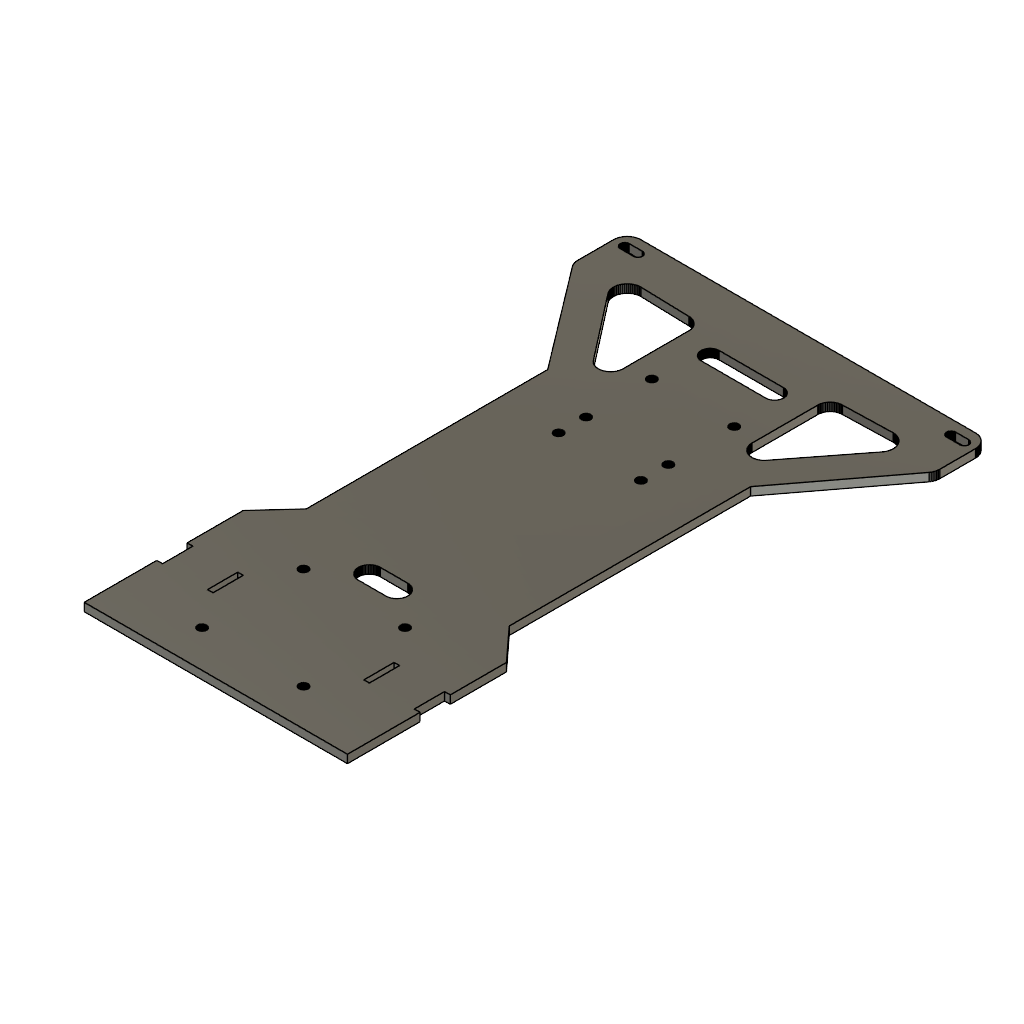
modelo-3d (Autodesk Fusion 360 archive; units mm, degrees)
design "Robot sigue lineas1"
part number: 2026-11-21-15-19-23-234
Autodesk Fusion 360 part; units mm, degrees
(part 1 of 2)
sketch "Sketch1" plane through (0, 0, 0) normal (0, 0, 1) x (1, 0, 0)
  line L0 (48, 26.5) -> (45.9, 26.5)
  line L1 (45.9, 26.5) -> (45.9, 37.5)
  line L2 (45.9, 37.5) -> (48, 37.5)
  line L3 (48, 37.5) -> (48, 58)
  line L4 (48, 58) -> (37, 70)
  line L5 (37, 70) -> (37, 158)
  line L6 (37, 158) -> (65.0451, 195.061)
  line L7 (65.0451, 195.061) -> (65.3301, 195.5)
  line L8 (65.3301, 195.5) -> (65.5677, 195.966)
  line L9 (65.5677, 195.966) -> (65.7553, 196.455)
  line L10 (65.7553, 196.455) -> (65.8907, 196.96)
  line L11 (65.8907, 196.96) -> (65.9726, 197.477)
  line L12 (65.9726, 197.477) -> (66, 198)
  line L13 (66, 198) -> (66, 211)
  line L14 (66, 211) -> (65.9726, 211.523)
  line L15 (65.9726, 211.523) -> (65.8907, 212.04)
  line L16 (65.8907, 212.04) -> (65.7553, 212.545)
  line L17 (65.7553, 212.545) -> (65.5677, 213.034)
  line L18 (65.5677, 213.034) -> (65.3301, 213.5)
  line L19 (65.3301, 213.5) -> (65.0451, 213.939)
  line L20 (65.0451, 213.939) -> (64.7157, 214.346)
  line L21 (64.7157, 214.346) -> (64.3457, 214.716)
  line L22 (64.3457, 214.716) -> (63.9389, 215.045)
  line L23 (63.9389, 215.045) -> (63.5, 215.33)
  line L24 (63.5, 215.33) -> (63.0337, 215.568)
  line L25 (63.0337, 215.568) -> (62.5451, 215.755)
  line L26 (62.5451, 215.755) -> (62.0396, 215.891)
  line L27 (62.0396, 215.891) -> (61.5226, 215.973)
  line L28 (61.5226, 215.973) -> (61, 216)
  line L29 (61, 216) -> (-61, 216)
  line L30 (-61, 216) -> (-61.5226, 215.973)
  line L31 (-61.5226, 215.973) -> (-62.0396, 215.891)
  line L32 (-62.0396, 215.891) -> (-62.5451, 215.755)
  line L33 (-62.5451, 215.755) -> (-63.0337, 215.568)
  line L34 (-63.0337, 215.568) -> (-63.5, 215.33)
  line L35 (-63.5, 215.33) -> (-63.9389, 215.045)
  line L36 (-63.9389, 215.045) -> (-64.3457, 214.716)
  line L37 (-64.3457, 214.716) -> (-64.7157, 214.346)
  line L38 (-64.7157, 214.346) -> (-65.0451, 213.939)
  line L39 (-65.0451, 213.939) -> (-65.3301, 213.5)
  line L40 (-65.3301, 213.5) -> (-65.5677, 213.034)
  line L41 (-65.5677, 213.034) -> (-65.7553, 212.545)
  line L42 (-65.7553, 212.545) -> (-65.8907, 212.04)
  line L43 (-65.8907, 212.04) -> (-65.9726, 211.523)
  line L44 (-65.9726, 211.523) -> (-66, 211)
  line L45 (-66, 211) -> (-66, 198)
  line L46 (-66, 198) -> (-65.9726, 197.477)
  line L47 (-65.9726, 197.477) -> (-65.8907, 196.96)
  line L48 (-65.8907, 196.96) -> (-65.7553, 196.455)
  line L49 (-65.7553, 196.455) -> (-65.5677, 195.966)
  line L50 (-65.5677, 195.966) -> (-65.3301, 195.5)
  line L51 (-65.3301, 195.5) -> (-65.0451, 195.061)
  line L52 (-65.0451, 195.061) -> (-37, 158)
  line L53 (-37, 158) -> (-37, 70)
  line L54 (-37, 70) -> (-48, 58)
  line L55 (-48, 58) -> (-48, 37.5)
  line L56 (-48, 37.5) -> (-45.9, 37.5)
  line L57 (-45.9, 37.5) -> (-45.9, 26.5)
  line L58 (-45.9, 26.5) -> (-48, 26.5)
  line L59 (-48, 26.5) -> (-48, 0)
  line L60 (-48, 0) -> (48, 0)
  line L61 (48, 0) -> (48, 26.5)
  line L62 (-61.9, 209.4) -> (-62.0672, 209.409)
  line L63 (-62.0672, 209.409) -> (-62.2327, 209.435)
  line L64 (-62.2327, 209.435) -> (-62.3944, 209.478)
  line L65 (-62.3944, 209.478) -> (-62.5508, 209.538)
  line L66 (-62.5508, 209.538) -> (-62.7, 209.614)
  line L67 (-62.7, 209.614) -> (-62.8405, 209.706)
  line L68 (-62.8405, 209.706) -> (-62.9706, 209.811)
  line L69 (-62.9706, 209.811) -> (-63.089, 209.929)
  line L70 (-63.089, 209.929) -> (-63.1944, 210.06)
  line L71 (-63.1944, 210.06) -> (-63.2856, 210.2)
  line L72 (-63.2856, 210.2) -> (-63.3617, 210.349)
  line L73 (-63.3617, 210.349) -> (-63.4217, 210.506)
  line L74 (-63.4217, 210.506) -> (-63.465, 210.667)
  line L75 (-63.465, 210.667) -> (-63.4912, 210.833)
  line L76 (-63.4912, 210.833) -> (-63.5, 211)
  line L77 (-63.5, 211) -> (-63.4912, 211.167)
  line L78 (-63.4912, 211.167) -> (-63.465, 211.333)
  line L79 (-63.465, 211.333) -> (-63.4217, 211.494)
  line L80 (-63.4217, 211.494) -> (-63.3617, 211.651)
  line L81 (-63.3617, 211.651) -> (-63.2856, 211.8)
  line L82 (-63.2856, 211.8) -> (-63.1944, 211.94)
  line L83 (-63.1944, 211.94) -> (-63.089, 212.071)
  line L84 (-63.089, 212.071) -> (-62.9706, 212.189)
  line L85 (-62.9706, 212.189) -> (-62.8405, 212.294)
  line L86 (-62.8405, 212.294) -> (-62.7, 212.386)
  line L87 (-62.7, 212.386) -> (-62.5508, 212.462)
  line L88 (-62.5508, 212.462) -> (-62.3944, 212.522)
  line L89 (-62.3944, 212.522) -> (-62.2327, 212.565)
  line L90 (-62.2327, 212.565) -> (-62.0672, 212.591)
  line L91 (-62.0672, 212.591) -> (-61.9, 212.6)
  line L92 (-61.9, 212.6) -> (-57.1, 212.6)
  line L93 (-57.1, 212.6) -> (-56.9328, 212.591)
  line L94 (-56.9328, 212.591) -> (-56.7673, 212.565)
  line L95 (-56.7673, 212.565) -> (-56.6056, 212.522)
  line L96 (-56.6056, 212.522) -> (-56.4492, 212.462)
  line L97 (-56.4492, 212.462) -> (-56.3, 212.386)
  line L98 (-56.3, 212.386) -> (-56.1595, 212.294)
  line L99 (-56.1595, 212.294) -> (-56.0294, 212.189)
  line L100 (-56.0294, 212.189) -> (-55.911, 212.071)
  line L101 (-55.911, 212.071) -> (-55.8056, 211.94)
  line L102 (-55.8056, 211.94) -> (-55.7144, 211.8)
  line L103 (-55.7144, 211.8) -> (-55.6383, 211.651)
  line L104 (-55.6383, 211.651) -> (-55.5783, 211.494)
  line L105 (-55.5783, 211.494) -> (-55.535, 211.333)
  line L106 (-55.535, 211.333) -> (-55.5088, 211.167)
  line L107 (-55.5088, 211.167) -> (-55.5, 211)
  line L108 (-55.5, 211) -> (-55.5088, 210.833)
  line L109 (-55.5088, 210.833) -> (-55.535, 210.667)
  line L110 (-55.535, 210.667) -> (-55.5783, 210.506)
  line L111 (-55.5783, 210.506) -> (-55.6383, 210.349)
  line L112 (-55.6383, 210.349) -> (-55.7144, 210.2)
  line L113 (-55.7144, 210.2) -> (-55.8056, 210.06)
  line L114 (-55.8056, 210.06) -> (-55.911, 209.929)
  line L115 (-55.911, 209.929) -> (-56.0294, 209.811)
  line L116 (-56.0294, 209.811) -> (-56.1595, 209.706)
  line L117 (-56.1595, 209.706) -> (-56.3, 209.614)
  line L118 (-56.3, 209.614) -> (-56.4492, 209.538)
  line L119 (-56.4492, 209.538) -> (-56.6056, 209.478)
  line L120 (-56.6056, 209.478) -> (-56.7673, 209.435)
  line L121 (-56.7673, 209.435) -> (-56.9328, 209.409)
  line L122 (-56.9328, 209.409) -> (-57.1, 209.4)
  line L123 (-57.1, 209.4) -> (-61.9, 209.4)
  line L124 (57.1, 209.4) -> (56.9328, 209.409)
  line L125 (56.9328, 209.409) -> (56.7673, 209.435)
  line L126 (56.7673, 209.435) -> (56.6056, 209.478)
  line L127 (56.6056, 209.478) -> (56.4492, 209.538)
  line L128 (56.4492, 209.538) -> (56.3, 209.614)
  line L129 (56.3, 209.614) -> (56.1595, 209.706)
  line L130 (56.1595, 209.706) -> (56.0294, 209.811)
  line L131 (56.0294, 209.811) -> (55.911, 209.929)
  line L132 (55.911, 209.929) -> (55.8056, 210.06)
  line L133 (55.8056, 210.06) -> (55.7144, 210.2)
  line L134 (55.7144, 210.2) -> (55.6383, 210.349)
  line L135 (55.6383, 210.349) -> (55.5783, 210.506)
  line L136 (55.5783, 210.506) -> (55.535, 210.667)
  line L137 (55.535, 210.667) -> (55.5088, 210.833)
  line L138 (55.5088, 210.833) -> (55.5, 211)
  line L139 (55.5, 211) -> (55.5088, 211.167)
  line L140 (55.5088, 211.167) -> (55.535, 211.333)
  line L141 (55.535, 211.333) -> (55.5783, 211.494)
  line L142 (55.5783, 211.494) -> (55.6383, 211.651)
  line L143 (55.6383, 211.651) -> (55.7144, 211.8)
  line L144 (55.7144, 211.8) -> (55.8056, 211.94)
  line L145 (55.8056, 211.94) -> (55.911, 212.071)
  line L146 (55.911, 212.071) -> (56.0294, 212.189)
  line L147 (56.0294, 212.189) -> (56.1595, 212.294)
  line L148 (56.1595, 212.294) -> (56.3, 212.386)
  line L149 (56.3, 212.386) -> (56.4492, 212.462)
  line L150 (56.4492, 212.462) -> (56.6056, 212.522)
  line L151 (56.6056, 212.522) -> (56.7673, 212.565)
  line L152 (56.7673, 212.565) -> (56.9328, 212.591)
  line L153 (56.9328, 212.591) -> (57.1, 212.6)
  line L154 (57.1, 212.6) -> (61.9, 212.6)
  line L155 (61.9, 212.6) -> (62.0672, 212.591)
  line L156 (62.0672, 212.591) -> (62.2327, 212.565)
  line L157 (62.2327, 212.565) -> (62.3944, 212.522)
  line L158 (62.3944, 212.522) -> (62.5508, 212.462)
  line L159 (62.5508, 212.462) -> (62.7, 212.386)
  line L160 (62.7, 212.386) -> (62.8405, 212.294)
  line L161 (62.8405, 212.294) -> (62.9706, 212.189)
  line L162 (62.9706, 212.189) -> (63.089, 212.071)
  line L163 (63.089, 212.071) -> (63.1944, 211.94)
  line L164 (63.1944, 211.94) -> (63.2856, 211.8)
  line L165 (63.2856, 211.8) -> (63.3617, 211.651)
  line L166 (63.3617, 211.651) -> (63.4217, 211.494)
  line L167 (63.4217, 211.494) -> (63.465, 211.333)
  line L168 (63.465, 211.333) -> (63.4912, 211.167)
  line L169 (63.4912, 211.167) -> (63.5, 211)
  line L170 (63.5, 211) -> (63.4912, 210.833)
  line L171 (63.4912, 210.833) -> (63.465, 210.667)
  line L172 (63.465, 210.667) -> (63.4217, 210.506)
  line L173 (63.4217, 210.506) -> (63.3617, 210.349)
  line L174 (63.3617, 210.349) -> (63.2856, 210.2)
  line L175 (63.2856, 210.2) -> (63.1944, 210.06)
  line L176 (63.1944, 210.06) -> (63.089, 209.929)
  line L177 (63.089, 209.929) -> (62.9706, 209.811)
  line L178 (62.9706, 209.811) -> (62.8405, 209.706)
  line L179 (62.8405, 209.706) -> (62.7, 209.614)
  line L180 (62.7, 209.614) -> (62.5508, 209.538)
  line L181 (62.5508, 209.538) -> (62.3944, 209.478)
  line L182 (62.3944, 209.478) -> (62.2327, 209.435)
  line L183 (62.2327, 209.435) -> (62.0672, 209.409)
  line L184 (62.0672, 209.409) -> (61.9, 209.4)
  line L185 (61.9, 209.4) -> (57.1, 209.4)
  line L186 (-28.4704, 167.525) -> (-28.9356, 167.598)
  line L187 (-28.9356, 167.598) -> (-29.3906, 167.72)
  line L188 (-29.3906, 167.72) -> (-29.8303, 167.889)
  line L189 (-29.8303, 167.889) -> (-30.25, 168.103)
  line L190 (-30.25, 168.103) -> (-30.645, 168.359)
  line L191 (-30.645, 168.359) -> (-31.0111, 168.656)
  line L192 (-31.0111, 168.656) -> (-31.3442, 168.989)
  line L193 (-31.3442, 168.989) -> (-31.6406, 169.355)
  line L194 (-31.6406, 169.355) -> (-50.0451, 193.061)
  line L195 (-50.0451, 193.061) -> (-50.3301, 193.5)
  line L196 (-50.3301, 193.5) -> (-50.5677, 193.966)
  line L197 (-50.5677, 193.966) -> (-50.7553, 194.455)
  line L198 (-50.7553, 194.455) -> (-50.8907, 194.96)
  line L199 (-50.8907, 194.96) -> (-50.9726, 195.477)
  line L200 (-50.9726, 195.477) -> (-51, 196)
  line L201 (-51, 196) -> (-50.9726, 196.523)
  line L202 (-50.9726, 196.523) -> (-50.8907, 197.04)
  line L203 (-50.8907, 197.04) -> (-50.7553, 197.545)
  line L204 (-50.7553, 197.545) -> (-50.5677, 198.034)
  line L205 (-50.5677, 198.034) -> (-50.3301, 198.5)
  line L206 (-50.3301, 198.5) -> (-50.0451, 198.939)
  line L207 (-50.0451, 198.939) -> (-49.7157, 199.346)
  line L208 (-49.7157, 199.346) -> (-49.3457, 199.716)
  line L209 (-49.3457, 199.716) -> (-48.9389, 200.045)
  line L210 (-48.9389, 200.045) -> (-48.5, 200.33)
  line L211 (-48.5, 200.33) -> (-48.0337, 200.568)
  line L212 (-48.0337, 200.568) -> (-47.5451, 200.755)
  line L213 (-47.5451, 200.755) -> (-47.0396, 200.891)
  line L214 (-47.0396, 200.891) -> (-46.5226, 200.973)
  line L215 (-46.5226, 200.973) -> (-46, 201)
  line L216 (-46, 201) -> (-28, 200.5)
  line L217 (-28, 200.5) -> (-27.5296, 200.475)
  line L218 (-27.5296, 200.475) -> (-27.0644, 200.402)
  line L219 (-27.0644, 200.402) -> (-26.6094, 200.28)
  line L220 (-26.6094, 200.28) -> (-26.1697, 200.111)
  line L221 (-26.1697, 200.111) -> (-25.75, 199.897)
  line L222 (-25.75, 199.897) -> (-25.355, 199.641)
  line L223 (-25.355, 199.641) -> (-24.9889, 199.344)
  line L224 (-24.9889, 199.344) -> (-24.6558, 199.011)
  line L225 (-24.6558, 199.011) -> (-24.3594, 198.645)
  line L226 (-24.3594, 198.645) -> (-24.1029, 198.25)
  line L227 (-24.1029, 198.25) -> (-23.889, 197.83)
  line L228 (-23.889, 197.83) -> (-23.7202, 197.391)
  line L229 (-23.7202, 197.391) -> (-23.5983, 196.936)
  line L230 (-23.5983, 196.936) -> (-23.5247, 196.47)
  line L231 (-23.5247, 196.47) -> (-23.5, 196)
  line L232 (-23.5, 196) -> (-23.5, 172)
  line L233 (-23.5, 172) -> (-23.5247, 171.53)
  line L234 (-23.5247, 171.53) -> (-23.5983, 171.064)
  line L235 (-23.5983, 171.064) -> (-23.7202, 170.609)
  line L236 (-23.7202, 170.609) -> (-23.889, 170.17)
  line L237 (-23.889, 170.17) -> (-24.1029, 169.75)
  line L238 (-24.1029, 169.75) -> (-24.3594, 169.355)
  line L239 (-24.3594, 169.355) -> (-24.6558, 168.989)
  line L240 (-24.6558, 168.989) -> (-24.9889, 168.656)
  line L241 (-24.9889, 168.656) -> (-25.355, 168.359)
  line L242 (-25.355, 168.359) -> (-25.75, 168.103)
  line L243 (-25.75, 168.103) -> (-26.1697, 167.889)
  line L244 (-26.1697, 167.889) -> (-26.6094, 167.72)
  line L245 (-26.6094, 167.72) -> (-27.0644, 167.598)
  line L246 (-27.0644, 167.598) -> (-27.5296, 167.525)
  line L247 (-27.5296, 167.525) -> (-28, 167.5)
  line L248 (-28, 167.5) -> (-28.4704, 167.525)
  line L249 (27.5296, 167.525) -> (27.0644, 167.598)
  line L250 (27.0644, 167.598) -> (26.6094, 167.72)
  line L251 (26.6094, 167.72) -> (26.1697, 167.889)
  line L252 (26.1697, 167.889) -> (25.75, 168.103)
  line L253 (25.75, 168.103) -> (25.355, 168.359)
  line L254 (25.355, 168.359) -> (24.9889, 168.656)
  line L255 (24.9889, 168.656) -> (24.6558, 168.989)
  line L256 (24.6558, 168.989) -> (24.3594, 169.355)
  line L257 (24.3594, 169.355) -> (24.1029, 169.75)
  line L258 (24.1029, 169.75) -> (23.889, 170.17)
  line L259 (23.889, 170.17) -> (23.7202, 170.609)
  line L260 (23.7202, 170.609) -> (23.5983, 171.064)
  line L261 (23.5983, 171.064) -> (23.5247, 171.53)
  line L262 (23.5247, 171.53) -> (23.5, 172)
  line L263 (23.5, 172) -> (23.5, 196)
  line L264 (23.5, 196) -> (23.5247, 196.47)
  line L265 (23.5247, 196.47) -> (23.5983, 196.936)
  line L266 (23.5983, 196.936) -> (23.7202, 197.391)
  line L267 (23.7202, 197.391) -> (23.889, 197.83)
  line L268 (23.889, 197.83) -> (24.1029, 198.25)
  line L269 (24.1029, 198.25) -> (24.3594, 198.645)
  line L270 (24.3594, 198.645) -> (24.6558, 199.011)
  line L271 (24.6558, 199.011) -> (24.9889, 199.344)
  line L272 (24.9889, 199.344) -> (25.355, 199.641)
  line L273 (25.355, 199.641) -> (25.75, 199.897)
  line L274 (25.75, 199.897) -> (26.1697, 200.111)
  line L275 (26.1697, 200.111) -> (26.6094, 200.28)
  line L276 (26.6094, 200.28) -> (27.0644, 200.402)
  line L277 (27.0644, 200.402) -> (27.5296, 200.475)
  line L278 (27.5296, 200.475) -> (28, 200.5)
  line L279 (28, 200.5) -> (46, 201)
  line L280 (46, 201) -> (46.5226, 200.973)
  line L281 (46.5226, 200.973) -> (47.0396, 200.891)
  line L282 (47.0396, 200.891) -> (47.5451, 200.755)
  line L283 (47.5451, 200.755) -> (48.0337, 200.568)
  line L284 (48.0337, 200.568) -> (48.5, 200.33)
  line L285 (48.5, 200.33) -> (48.9389, 200.045)
  line L286 (48.9389, 200.045) -> (49.3457, 199.716)
  line L287 (49.3457, 199.716) -> (49.7157, 199.346)
  line L288 (49.7157, 199.346) -> (50.0451, 198.939)
  line L289 (50.0451, 198.939) -> (50.3301, 198.5)
  line L290 (50.3301, 198.5) -> (50.5677, 198.034)
  line L291 (50.5677, 198.034) -> (50.7553, 197.545)
  line L292 (50.7553, 197.545) -> (50.8907, 197.04)
  line L293 (50.8907, 197.04) -> (50.9726, 196.523)
  line L294 (50.9726, 196.523) -> (51, 196)
  line L295 (51, 196) -> (50.9726, 195.477)
  line L296 (50.9726, 195.477) -> (50.8907, 194.96)
  line L297 (50.8907, 194.96) -> (50.7553, 194.455)
  line L298 (50.7553, 194.455) -> (50.5677, 193.966)
  line L299 (50.5677, 193.966) -> (50.3301, 193.5)
  line L300 (50.3301, 193.5) -> (50.0451, 193.061)
  line L301 (50.0451, 193.061) -> (31.6406, 169.355)
  line L302 (31.6406, 169.355) -> (31.3442, 168.989)
  line L303 (31.3442, 168.989) -> (31.0111, 168.656)
  line L304 (31.0111, 168.656) -> (30.645, 168.359)
  line L305 (30.645, 168.359) -> (30.25, 168.103)
  line L306 (30.25, 168.103) -> (29.8303, 167.889)
  line L307 (29.8303, 167.889) -> (29.3906, 167.72)
  line L308 (29.3906, 167.72) -> (28.9356, 167.598)
  line L309 (28.9356, 167.598) -> (28.4704, 167.525)
  line L310 (28.4704, 167.525) -> (28, 167.5)
  line L311 (28, 167.5) -> (27.5296, 167.525)
  line L312 (-11.75, 188.75) -> (-12.0897, 188.768)
  line L313 (-12.0897, 188.768) -> (-12.4257, 188.821)
  line L314 (-12.4257, 188.821) -> (-12.7543, 188.909)
  line L315 (-12.7543, 188.909) -> (-13.0719, 189.031)
  line L316 (-13.0719, 189.031) -> (-13.375, 189.185)
  line L317 (-13.375, 189.185) -> (-13.6603, 189.371)
  line L318 (-13.6603, 189.371) -> (-13.9247, 189.585)
  line L319 (-13.9247, 189.585) -> (-14.1652, 189.825)
  line L320 (-14.1652, 189.825) -> (-14.3793, 190.09)
  line L321 (-14.3793, 190.09) -> (-14.5646, 190.375)
  line L322 (-14.5646, 190.375) -> (-14.719, 190.678)
  line L323 (-14.719, 190.678) -> (-14.8409, 190.996)
  line L324 (-14.8409, 190.996) -> (-14.929, 191.324)
  line L325 (-14.929, 191.324) -> (-14.9822, 191.66)
  line L326 (-14.9822, 191.66) -> (-15, 192)
  line L327 (-15, 192) -> (-14.9822, 192.34)
  line L328 (-14.9822, 192.34) -> (-14.929, 192.676)
  line L329 (-14.929, 192.676) -> (-14.8409, 193.004)
  line L330 (-14.8409, 193.004) -> (-14.719, 193.322)
  line L331 (-14.719, 193.322) -> (-14.5646, 193.625)
  line L332 (-14.5646, 193.625) -> (-14.3793, 193.91)
  line L333 (-14.3793, 193.91) -> (-14.1652, 194.175)
  line L334 (-14.1652, 194.175) -> (-13.9247, 194.415)
  line L335 (-13.9247, 194.415) -> (-13.6603, 194.629)
  line L336 (-13.6603, 194.629) -> (-13.375, 194.815)
  line L337 (-13.375, 194.815) -> (-13.0719, 194.969)
  line L338 (-13.0719, 194.969) -> (-12.7543, 195.091)
  line L339 (-12.7543, 195.091) -> (-12.4257, 195.179)
  line L340 (-12.4257, 195.179) -> (-12.0897, 195.232)
  line L341 (-12.0897, 195.232) -> (-11.75, 195.25)
  line L342 (-11.75, 195.25) -> (11.75, 195.25)
  line L343 (11.75, 195.25) -> (12.0897, 195.232)
  line L344 (12.0897, 195.232) -> (12.4257, 195.179)
  line L345 (12.4257, 195.179) -> (12.7543, 195.091)
  line L346 (12.7543, 195.091) -> (13.0719, 194.969)
  line L347 (13.0719, 194.969) -> (13.375, 194.815)
  line L348 (13.375, 194.815) -> (13.6603, 194.629)
  line L349 (13.6603, 194.629) -> (13.9247, 194.415)
  line L350 (13.9247, 194.415) -> (14.1652, 194.175)
  line L351 (14.1652, 194.175) -> (14.3793, 193.91)
  line L352 (14.3793, 193.91) -> (14.5646, 193.625)
  line L353 (14.5646, 193.625) -> (14.719, 193.322)
  line L354 (14.719, 193.322) -> (14.8409, 193.004)
  line L355 (14.8409, 193.004) -> (14.929, 192.676)
  line L356 (14.929, 192.676) -> (14.9822, 192.34)
  line L357 (14.9822, 192.34) -> (15, 192)
  line L358 (15, 192) -> (14.9822, 191.66)
  line L359 (14.9822, 191.66) -> (14.929, 191.324)
  line L360 (14.929, 191.324) -> (14.8409, 190.996)
  line L361 (14.8409, 190.996) -> (14.719, 190.678)
  line L362 (14.719, 190.678) -> (14.5646, 190.375)
  line L363 (14.5646, 190.375) -> (14.3793, 190.09)
  line L364 (14.3793, 190.09) -> (14.1652, 189.825)
  line L365 (14.1652, 189.825) -> (13.9247, 189.585)
  line L366 (13.9247, 189.585) -> (13.6603, 189.371)
  line L367 (13.6603, 189.371) -> (13.375, 189.185)
  line L368 (13.375, 189.185) -> (13.0719, 189.031)
  line L369 (13.0719, 189.031) -> (12.7543, 188.909)
  line L370 (12.7543, 188.909) -> (12.4257, 188.821)
  line L371 (12.4257, 188.821) -> (12.0897, 188.768)
  line L372 (12.0897, 188.768) -> (11.75, 188.75)
  line L373 (11.75, 188.75) -> (-11.75, 188.75)
  line L374 (-15.1672, 172.409) -> (-15.3327, 172.435)
  line L375 (-15.3327, 172.435) -> (-15.4944, 172.478)
  line L376 (-15.4944, 172.478) -> (-15.6508, 172.538)
  line L377 (-15.6508, 172.538) -> (-15.8, 172.614)
  line L378 (-15.8, 172.614) -> (-15.9405, 172.706)
  line L379 (-15.9405, 172.706) -> (-16.0706, 172.811)
  line L380 (-16.0706, 172.811) -> (-16.189, 172.929)
  line L381 (-16.189, 172.929) -> (-16.2944, 173.06)
  line L382 (-16.2944, 173.06) -> (-16.3856, 173.2)
  line L383 (-16.3856, 173.2) -> (-16.4617, 173.349)
  line L384 (-16.4617, 173.349) -> (-16.5217, 173.506)
  line L385 (-16.5217, 173.506) -> (-16.565, 173.667)
  line L386 (-16.565, 173.667) -> (-16.5912, 173.833)
  line L387 (-16.5912, 173.833) -> (-16.6, 174)
  line L388 (-16.6, 174) -> (-16.5912, 174.167)
  line L389 (-16.5912, 174.167) -> (-16.565, 174.333)
  line L390 (-16.565, 174.333) -> (-16.5217, 174.494)
  line L391 (-16.5217, 174.494) -> (-16.4617, 174.651)
  line L392 (-16.4617, 174.651) -> (-16.3856, 174.8)
  line L393 (-16.3856, 174.8) -> (-16.2944, 174.94)
  line L394 (-16.2944, 174.94) -> (-16.189, 175.071)
  line L395 (-16.189, 175.071) -> (-16.0706, 175.189)
  line L396 (-16.0706, 175.189) -> (-15.9405, 175.294)
  line L397 (-15.9405, 175.294) -> (-15.8, 175.386)
  line L398 (-15.8, 175.386) -> (-15.6508, 175.462)
  line L399 (-15.6508, 175.462) -> (-15.4944, 175.522)
  line L400 (-15.4944, 175.522) -> (-15.3327, 175.565)
  line L401 (-15.3327, 175.565) -> (-15.1672, 175.591)
  line L402 (-15.1672, 175.591) -> (-15, 175.6)
  line L403 (-15, 175.6) -> (-14.8328, 175.591)
  line L404 (-14.8328, 175.591) -> (-14.6673, 175.565)
  line L405 (-14.6673, 175.565) -> (-14.5056, 175.522)
  line L406 (-14.5056, 175.522) -> (-14.3492, 175.462)
  line L407 (-14.3492, 175.462) -> (-14.2, 175.386)
  line L408 (-14.2, 175.386) -> (-14.0595, 175.294)
  line L409 (-14.0595, 175.294) -> (-13.9294, 175.189)
  line L410 (-13.9294, 175.189) -> (-13.811, 175.071)
  line L411 (-13.811, 175.071) -> (-13.7056, 174.94)
  line L412 (-13.7056, 174.94) -> (-13.6144, 174.8)
  line L413 (-13.6144, 174.8) -> (-13.5383, 174.651)
  line L414 (-13.5383, 174.651) -> (-13.4783, 174.494)
  line L415 (-13.4783, 174.494) -> (-13.435, 174.333)
  line L416 (-13.435, 174.333) -> (-13.4088, 174.167)
  line L417 (-13.4088, 174.167) -> (-13.4, 174)
  line L418 (-13.4, 174) -> (-13.4088, 173.833)
  line L419 (-13.4088, 173.833) -> (-13.435, 173.667)
  line L420 (-13.435, 173.667) -> (-13.4783, 173.506)
  line L421 (-13.4783, 173.506) -> (-13.5383, 173.349)
  line L422 (-13.5383, 173.349) -> (-13.6144, 173.2)
  line L423 (-13.6144, 173.2) -> (-13.7056, 173.06)
  line L424 (-13.7056, 173.06) -> (-13.811, 172.929)
  line L425 (-13.811, 172.929) -> (-13.9294, 172.811)
  line L426 (-13.9294, 172.811) -> (-14.0595, 172.706)
  line L427 (-14.0595, 172.706) -> (-14.2, 172.614)
  line L428 (-14.2, 172.614) -> (-14.3492, 172.538)
  line L429 (-14.3492, 172.538) -> (-14.5056, 172.478)
  line L430 (-14.5056, 172.478) -> (-14.6673, 172.435)
  line L431 (-14.6673, 172.435) -> (-14.8328, 172.409)
  line L432 (-14.8328, 172.409) -> (-15, 172.4)
  line L433 (-15, 172.4) -> (-15.1672, 172.409)
  line L434 (14.8328, 172.409) -> (14.6673, 172.435)
  line L435 (14.6673, 172.435) -> (14.5056, 172.478)
  line L436 (14.5056, 172.478) -> (14.3492, 172.538)
  line L437 (14.3492, 172.538) -> (14.2, 172.614)
  line L438 (14.2, 172.614) -> (14.0595, 172.706)
  line L439 (14.0595, 172.706) -> (13.9294, 172.811)
  line L440 (13.9294, 172.811) -> (13.811, 172.929)
  line L441 (13.811, 172.929) -> (13.7056, 173.06)
  line L442 (13.7056, 173.06) -> (13.6144, 173.2)
  line L443 (13.6144, 173.2) -> (13.5383, 173.349)
  line L444 (13.5383, 173.349) -> (13.4783, 173.506)
  line L445 (13.4783, 173.506) -> (13.435, 173.667)
  line L446 (13.435, 173.667) -> (13.4088, 173.833)
  line L447 (13.4088, 173.833) -> (13.4, 174)
  line L448 (13.4, 174) -> (13.4088, 174.167)
  line L449 (13.4088, 174.167) -> (13.435, 174.333)
  line L450 (13.435, 174.333) -> (13.4783, 174.494)
  line L451 (13.4783, 174.494) -> (13.5383, 174.651)
  line L452 (13.5383, 174.651) -> (13.6144, 174.8)
  line L453 (13.6144, 174.8) -> (13.7056, 174.94)
  line L454 (13.7056, 174.94) -> (13.811, 175.071)
  line L455 (13.811, 175.071) -> (13.9294, 175.189)
  line L456 (13.9294, 175.189) -> (14.0595, 175.294)
  line L457 (14.0595, 175.294) -> (14.2, 175.386)
  line L458 (14.2, 175.386) -> (14.3492, 175.462)
  line L459 (14.3492, 175.462) -> (14.5056, 175.522)
  line L460 (14.5056, 175.522) -> (14.6673, 175.565)
  line L461 (14.6673, 175.565) -> (14.8328, 175.591)
  line L462 (14.8328, 175.591) -> (15, 175.6)
  line L463 (15, 175.6) -> (15.1672, 175.591)
  line L464 (15.1672, 175.591) -> (15.3327, 175.565)
  line L465 (15.3327, 175.565) -> (15.4944, 175.522)
  line L466 (15.4944, 175.522) -> (15.6508, 175.462)
  line L467 (15.6508, 175.462) -> (15.8, 175.386)
  line L468 (15.8, 175.386) -> (15.9405, 175.294)
  line L469 (15.9405, 175.294) -> (16.0706, 175.189)
  line L470 (16.0706, 175.189) -> (16.189, 175.071)
  line L471 (16.189, 175.071) -> (16.2944, 174.94)
  line L472 (16.2944, 174.94) -> (16.3856, 174.8)
  line L473 (16.3856, 174.8) -> (16.4617, 174.651)
  line L474 (16.4617, 174.651) -> (16.5217, 174.494)
  line L475 (16.5217, 174.494) -> (16.565, 174.333)
  line L476 (16.565, 174.333) -> (16.5912, 174.167)
  line L477 (16.5912, 174.167) -> (16.6, 174)
  line L478 (16.6, 174) -> (16.5912, 173.833)
  line L479 (16.5912, 173.833) -> (16.565, 173.667)
  line L480 (16.565, 173.667) -> (16.5217, 173.506)
  line L481 (16.5217, 173.506) -> (16.4617, 173.349)
  line L482 (16.4617, 173.349) -> (16.3856, 173.2)
  line L483 (16.3856, 173.2) -> (16.2944, 173.06)
  line L484 (16.2944, 173.06) -> (16.189, 172.929)
  line L485 (16.189, 172.929) -> (16.0706, 172.811)
  line L486 (16.0706, 172.811) -> (15.9405, 172.706)
  line L487 (15.9405, 172.706) -> (15.8, 172.614)
  line L488 (15.8, 172.614) -> (15.6508, 172.538)
  line L489 (15.6508, 172.538) -> (15.4944, 172.478)
  line L490 (15.4944, 172.478) -> (15.3327, 172.435)
  line L491 (15.3327, 172.435) -> (15.1672, 172.409)
  line L492 (15.1672, 172.409) -> (15, 172.4)
  line L493 (15, 172.4) -> (14.8328, 172.409)
  line L494 (-15.1672, 148.409) -> (-15.3327, 148.435)
  line L495 (-15.3327, 148.435) -> (-15.4944, 148.478)
  line L496 (-15.4944, 148.478) -> (-15.6508, 148.538)
  line L497 (-15.6508, 148.538) -> (-15.8, 148.614)
  line L498 (-15.8, 148.614) -> (-15.9405, 148.706)
  line L499 (-15.9405, 148.706) -> (-16.0706, 148.811)
  line L500 (-16.0706, 148.811) -> (-16.189, 148.929)
  line L501 (-16.189, 148.929) -> (-16.2944, 149.06)
  line L502 (-16.2944, 149.06) -> (-16.3856, 149.2)
  line L503 (-16.3856, 149.2) -> (-16.4617, 149.349)
  line L504 (-16.4617, 149.349) -> (-16.5217, 149.506)
  line L505 (-16.5217, 149.506) -> (-16.565, 149.667)
  line L506 (-16.565, 149.667) -> (-16.5912, 149.833)
  line L507 (-16.5912, 149.833) -> (-16.6, 150)
  line L508 (-16.6, 150) -> (-16.5912, 150.167)
  line L509 (-16.5912, 150.167) -> (-16.565, 150.333)
  line L510 (-16.565, 150.333) -> (-16.5217, 150.494)
  line L511 (-16.5217, 150.494) -> (-16.4617, 150.651)
  line L512 (-16.4617, 150.651) -> (-16.3856, 150.8)
  line L513 (-16.3856, 150.8) -> (-16.2944, 150.94)
  line L514 (-16.2944, 150.94) -> (-16.189, 151.071)
  line L515 (-16.189, 151.071) -> (-16.0706, 151.189)
  line L516 (-16.0706, 151.189) -> (-15.9405, 151.294)
  line L517 (-15.9405, 151.294) -> (-15.8, 151.386)
  line L518 (-15.8, 151.386) -> (-15.6508, 151.462)
  line L519 (-15.6508, 151.462) -> (-15.4944, 151.522)
  line L520 (-15.4944, 151.522) -> (-15.3327, 151.565)
  line L521 (-15.3327, 151.565) -> (-15.1672, 151.591)
  line L522 (-15.1672, 151.591) -> (-15, 151.6)
  line L523 (-15, 151.6) -> (-14.8328, 151.591)
  line L524 (-14.8328, 151.591) -> (-14.6673, 151.565)
  line L525 (-14.6673, 151.565) -> (-14.5056, 151.522)
  line L526 (-14.5056, 151.522) -> (-14.3492, 151.462)
  line L527 (-14.3492, 151.462) -> (-14.2, 151.386)
  line L528 (-14.2, 151.386) -> (-14.0595, 151.294)
  line L529 (-14.0595, 151.294) -> (-13.9294, 151.189)
  line L530 (-13.9294, 151.189) -> (-13.811, 151.071)
  line L531 (-13.811, 151.071) -> (-13.7056, 150.94)
  line L532 (-13.7056, 150.94) -> (-13.6144, 150.8)
  line L533 (-13.6144, 150.8) -> (-13.5383, 150.651)
  line L534 (-13.5383, 150.651) -> (-13.4783, 150.494)
  line L535 (-13.4783, 150.494) -> (-13.435, 150.333)
  line L536 (-13.435, 150.333) -> (-13.4088, 150.167)
  line L537 (-13.4088, 150.167) -> (-13.4, 150)
  line L538 (-13.4, 150) -> (-13.4088, 149.833)
  line L539 (-13.4088, 149.833) -> (-13.435, 149.667)
  line L540 (-13.435, 149.667) -> (-13.4783, 149.506)
  line L541 (-13.4783, 149.506) -> (-13.5383, 149.349)
  line L542 (-13.5383, 149.349) -> (-13.6144, 149.2)
  line L543 (-13.6144, 149.2) -> (-13.7056, 149.06)
  line L544 (-13.7056, 149.06) -> (-13.811, 148.929)
  line L545 (-13.811, 148.929) -> (-13.9294, 148.811)
  line L546 (-13.9294, 148.811) -> (-14.0595, 148.706)
  line L547 (-14.0595, 148.706) -> (-14.2, 148.614)
  line L548 (-14.2, 148.614) -> (-14.3492, 148.538)
  line L549 (-14.3492, 148.538) -> (-14.5056, 148.478)
  line L550 (-14.5056, 148.478) -> (-14.6673, 148.435)
  line L551 (-14.6673, 148.435) -> (-14.8328, 148.409)
  line L552 (-14.8328, 148.409) -> (-15, 148.4)
  line L553 (-15, 148.4) -> (-15.1672, 148.409)
  line L554 (14.8328, 148.409) -> (14.6673, 148.435)
  line L555 (14.6673, 148.435) -> (14.5056, 148.478)
  line L556 (14.5056, 148.478) -> (14.3492, 148.538)
  line L557 (14.3492, 148.538) -> (14.2, 148.614)
  line L558 (14.2, 148.614) -> (14.0595, 148.706)
  line L559 (14.0595, 148.706) -> (13.9294, 148.811)
  line L560 (13.9294, 148.811) -> (13.811, 148.929)
  line L561 (13.811, 148.929) -> (13.7056, 149.06)
  line L562 (13.7056, 149.06) -> (13.6144, 149.2)
  line L563 (13.6144, 149.2) -> (13.5383, 149.349)
  line L564 (13.5383, 149.349) -> (13.4783, 149.506)
  line L565 (13.4783, 149.506) -> (13.435, 149.667)
  line L566 (13.435, 149.667) -> (13.4088, 149.833)
  line L567 (13.4088, 149.833) -> (13.4, 150)
  line L568 (13.4, 150) -> (13.4088, 150.167)
  line L569 (13.4088, 150.167) -> (13.435, 150.333)
  line L570 (13.435, 150.333) -> (13.4783, 150.494)
  line L571 (13.4783, 150.494) -> (13.5383, 150.651)
  line L572 (13.5383, 150.651) -> (13.6144, 150.8)
  line L573 (13.6144, 150.8) -> (13.7056, 150.94)
  line L574 (13.7056, 150.94) -> (13.811, 151.071)
  line L575 (13.811, 151.071) -> (13.9294, 151.189)
  line L576 (13.9294, 151.189) -> (14.0595, 151.294)
  line L577 (14.0595, 151.294) -> (14.2, 151.386)
  line L578 (14.2, 151.386) -> (14.3492, 151.462)
  line L579 (14.3492, 151.462) -> (14.5056, 151.522)
  line L580 (14.5056, 151.522) -> (14.6673, 151.565)
  line L581 (14.6673, 151.565) -> (14.8328, 151.591)
  line L582 (14.8328, 151.591) -> (15, 151.6)
  line L583 (15, 151.6) -> (15.1672, 151.591)
  line L584 (15.1672, 151.591) -> (15.3327, 151.565)
  line L585 (15.3327, 151.565) -> (15.4944, 151.522)
  line L586 (15.4944, 151.522) -> (15.6508, 151.462)
  line L587 (15.6508, 151.462) -> (15.8, 151.386)
  line L588 (15.8, 151.386) -> (15.9405, 151.294)
  line L589 (15.9405, 151.294) -> (16.0706, 151.189)
  line L590 (16.0706, 151.189) -> (16.189, 151.071)
  line L591 (16.189, 151.071) -> (16.2944, 150.94)
  line L592 (16.2944, 150.94) -> (16.3856, 150.8)
  line L593 (16.3856, 150.8) -> (16.4617, 150.651)
  line L594 (16.4617, 150.651) -> (16.5217, 150.494)
  line L595 (16.5217, 150.494) -> (16.565, 150.333)
  line L596 (16.565, 150.333) -> (16.5912, 150.167)
  line L597 (16.5912, 150.167) -> (16.6, 150)
  line L598 (16.6, 150) -> (16.5912, 149.833)
  line L599 (16.5912, 149.833) -> (16.565, 149.667)
  line L600 (16.565, 149.667) -> (16.5217, 149.506)
  line L601 (16.5217, 149.506) -> (16.4617, 149.349)
  line L602 (16.4617, 149.349) -> (16.3856, 149.2)
  line L603 (16.3856, 149.2) -> (16.2944, 149.06)
  line L604 (16.2944, 149.06) -> (16.189, 148.929)
  line L605 (16.189, 148.929) -> (16.0706, 148.811)
  line L606 (16.0706, 148.811) -> (15.9405, 148.706)
  line L607 (15.9405, 148.706) -> (15.8, 148.614)
  line L608 (15.8, 148.614) -> (15.6508, 148.538)
  line L609 (15.6508, 148.538) -> (15.4944, 148.478)
  line L610 (15.4944, 148.478) -> (15.3327, 148.435)
  line L611 (15.3327, 148.435) -> (15.1672, 148.409)
  line L612 (15.1672, 148.409) -> (15, 148.4)
  line L613 (15, 148.4) -> (14.8328, 148.409)
  line L614 (-15.1672, 138.409) -> (-15.3327, 138.435)
  line L615 (-15.3327, 138.435) -> (-15.4944, 138.478)
  line L616 (-15.4944, 138.478) -> (-15.6508, 138.538)
  line L617 (-15.6508, 138.538) -> (-15.8, 138.614)
  line L618 (-15.8, 138.614) -> (-15.9405, 138.706)
  line L619 (-15.9405, 138.706) -> (-16.0706, 138.811)
  line L620 (-16.0706, 138.811) -> (-16.189, 138.929)
  line L621 (-16.189, 138.929) -> (-16.2944, 139.06)
  line L622 (-16.2944, 139.06) -> (-16.3856, 139.2)
  line L623 (-16.3856, 139.2) -> (-16.4617, 139.349)
  line L624 (-16.4617, 139.349) -> (-16.5217, 139.506)
  line L625 (-16.5217, 139.506) -> (-16.565, 139.667)
  line L626 (-16.565, 139.667) -> (-16.5912, 139.833)
  line L627 (-16.5912, 139.833) -> (-16.6, 140)
  line L628 (-16.6, 140) -> (-16.5912, 140.167)
  line L629 (-16.5912, 140.167) -> (-16.565, 140.333)
  line L630 (-16.565, 140.333) -> (-16.5217, 140.494)
  line L631 (-16.5217, 140.494) -> (-16.4617, 140.651)
  line L632 (-16.4617, 140.651) -> (-16.3856, 140.8)
  line L633 (-16.3856, 140.8) -> (-16.2944, 140.94)
  line L634 (-16.2944, 140.94) -> (-16.189, 141.071)
  line L635 (-16.189, 141.071) -> (-16.0706, 141.189)
  line L636 (-16.0706, 141.189) -> (-15.9405, 141.294)
  line L637 (-15.9405, 141.294) -> (-15.8, 141.386)
  line L638 (-15.8, 141.386) -> (-15.6508, 141.462)
  line L639 (-15.6508, 141.462) -> (-15.4944, 141.522)
  line L640 (-15.4944, 141.522) -> (-15.3327, 141.565)
  line L641 (-15.3327, 141.565) -> (-15.1672, 141.591)
  line L642 (-15.1672, 141.591) -> (-15, 141.6)
  line L643 (-15, 141.6) -> (-14.8328, 141.591)
  line L644 (-14.8328, 141.591) -> (-14.6673, 141.565)
  line L645 (-14.6673, 141.565) -> (-14.5056, 141.522)
  line L646 (-14.5056, 141.522) -> (-14.3492, 141.462)
  line L647 (-14.3492, 141.462) -> (-14.2, 141.386)
  line L648 (-14.2, 141.386) -> (-14.0595, 141.294)
  line L649 (-14.0595, 141.294) -> (-13.9294, 141.189)
  line L650 (-13.9294, 141.189) -> (-13.811, 141.071)
  line L651 (-13.811, 141.071) -> (-13.7056, 140.94)
  line L652 (-13.7056, 140.94) -> (-13.6144, 140.8)
  line L653 (-13.6144, 140.8) -> (-13.5383, 140.651)
  line L654 (-13.5383, 140.651) -> (-13.4783, 140.494)
  line L655 (-13.4783, 140.494) -> (-13.435, 140.333)
  line L656 (-13.435, 140.333) -> (-13.4088, 140.167)
  line L657 (-13.4088, 140.167) -> (-13.4, 140)
  line L658 (-13.4, 140) -> (-13.4088, 139.833)
  line L659 (-13.4088, 139.833) -> (-13.435, 139.667)
  line L660 (-13.435, 139.667) -> (-13.4783, 139.506)
  line L661 (-13.4783, 139.506) -> (-13.5383, 139.349)
  line L662 (-13.5383, 139.349) -> (-13.6144, 139.2)
  line L663 (-13.6144, 139.2) -> (-13.7056, 139.06)
  line L664 (-13.7056, 139.06) -> (-13.811, 138.929)
  line L665 (-13.811, 138.929) -> (-13.9294, 138.811)
  line L666 (-13.9294, 138.811) -> (-14.0595, 138.706)
  line L667 (-14.0595, 138.706) -> (-14.2, 138.614)
  line L668 (-14.2, 138.614) -> (-14.3492, 138.538)
  line L669 (-14.3492, 138.538) -> (-14.5056, 138.478)
  line L670 (-14.5056, 138.478) -> (-14.6673, 138.435)
  line L671 (-14.6673, 138.435) -> (-14.8328, 138.409)
  line L672 (-14.8328, 138.409) -> (-15, 138.4)
  line L673 (-15, 138.4) -> (-15.1672, 138.409)
  line L674 (14.8328, 138.409) -> (14.6673, 138.435)
  line L675 (14.6673, 138.435) -> (14.5056, 138.478)
  line L676 (14.5056, 138.478) -> (14.3492, 138.538)
  line L677 (14.3492, 138.538) -> (14.2, 138.614)
  line L678 (14.2, 138.614) -> (14.0595, 138.706)
  line L679 (14.0595, 138.706) -> (13.9294, 138.811)
  line L680 (13.9294, 138.811) -> (13.811, 138.929)
  line L681 (13.811, 138.929) -> (13.7056, 139.06)
  line L682 (13.7056, 139.06) -> (13.6144, 139.2)
  line L683 (13.6144, 139.2) -> (13.5383, 139.349)
  line L684 (13.5383, 139.349) -> (13.4783, 139.506)
  line L685 (13.4783, 139.506) -> (13.435, 139.667)
  line L686 (13.435, 139.667) -> (13.4088, 139.833)
  line L687 (13.4088, 139.833) -> (13.4, 140)
  line L688 (13.4, 140) -> (13.4088, 140.167)
  line L689 (13.4088, 140.167) -> (13.435, 140.333)
  line L690 (13.435, 140.333) -> (13.4783, 140.494)
  line L691 (13.4783, 140.494) -> (13.5383, 140.651)
  line L692 (13.5383, 140.651) -> (13.6144, 140.8)
  line L693 (13.6144, 140.8) -> (13.7056, 140.94)
  line L694 (13.7056, 140.94) -> (13.811, 141.071)
  line L695 (13.811, 141.071) -> (13.9294, 141.189)
  line L696 (13.9294, 141.189) -> (14.0595, 141.294)
  line L697 (14.0595, 141.294) -> (14.2, 141.386)
  line L698 (14.2, 141.386) -> (14.3492, 141.462)
  line L699 (14.3492, 141.462) -> (14.5056, 141.522)
  line L700 (14.5056, 141.522) -> (14.6673, 141.565)
  line L701 (14.6673, 141.565) -> (14.8328, 141.591)
  line L702 (14.8328, 141.591) -> (15, 141.6)
  line L703 (15, 141.6) -> (15.1672, 141.591)
  line L704 (15.1672, 141.591) -> (15.3327, 141.565)
  line L705 (15.3327, 141.565) -> (15.4944, 141.522)
  line L706 (15.4944, 141.522) -> (15.6508, 141.462)
  line L707 (15.6508, 141.462) -> (15.8, 141.386)
  line L708 (15.8, 141.386) -> (15.9405, 141.294)
  line L709 (15.9405, 141.294) -> (16.0706, 141.189)
  line L710 (16.0706, 141.189) -> (16.189, 141.071)
  line L711 (16.189, 141.071) -> (16.2944, 140.94)
  line L712 (16.2944, 140.94) -> (16.3856, 140.8)
  line L713 (16.3856, 140.8) -> (16.4617, 140.651)
  line L714 (16.4617, 140.651) -> (16.5217, 140.494)
  line L715 (16.5217, 140.494) -> (16.565, 140.333)
  line L716 (16.565, 140.333) -> (16.5912, 140.167)
  line L717 (16.5912, 140.167) -> (16.6, 140)
  line L718 (16.6, 140) -> (16.5912, 139.833)
  line L719 (16.5912, 139.833) -> (16.565, 139.667)
  line L720 (16.565, 139.667) -> (16.5217, 139.506)
  line L721 (16.5217, 139.506) -> (16.4617, 139.349)
  line L722 (16.4617, 139.349) -> (16.3856, 139.2)
  line L723 (16.3856, 139.2) -> (16.2944, 139.06)
  line L724 (16.2944, 139.06) -> (16.189, 138.929)
  line L725 (16.189, 138.929) -> (16.0706, 138.811)
  line L726 (16.0706, 138.811) -> (15.9405, 138.706)
  line L727 (15.9405, 138.706) -> (15.8, 138.614)
  line L728 (15.8, 138.614) -> (15.6508, 138.538)
  line L729 (15.6508, 138.538) -> (15.4944, 138.478)
  line L730 (15.4944, 138.478) -> (15.3327, 138.435)
  line L731 (15.3327, 138.435) -> (15.1672, 138.409)
  line L732 (15.1672, 138.409) -> (15, 138.4)
  line L733 (15, 138.4) -> (14.8328, 138.409)
  line L734 (-5, 57) -> (-5.4181, 57.0219)
  line L735 (-5.4181, 57.0219) -> (-5.8316, 57.0874)
  line L736 (-5.8316, 57.0874) -> (-6.2361, 57.1958)
  line L737 (-6.2361, 57.1958) -> (-6.6269, 57.3458)
  line L738 (-6.6269, 57.3458) -> (-7, 57.5359)
  line L739 (-7, 57.5359) -> (-7.3511, 57.7639)
  line L740 (-7.3511, 57.7639) -> (-7.6765, 58.0274)
  line L741 (-7.6765, 58.0274) -> (-7.9726, 58.3235)
  line L742 (-7.9726, 58.3235) -> (-8.2361, 58.6489)
  line L743 (-8.2361, 58.6489) -> (-8.4641, 59)
  line L744 (-8.4641, 59) -> (-8.6542, 59.3731)
  line L745 (-8.6542, 59.3731) -> (-8.8042, 59.7639)
  line L746 (-8.8042, 59.7639) -> (-8.9126, 60.1684)
  line L747 (-8.9126, 60.1684) -> (-8.9781, 60.5819)
  line L748 (-8.9781, 60.5819) -> (-9, 61)
  line L749 (-9, 61) -> (-8.9781, 61.4181)
  line L750 (-8.9781, 61.4181) -> (-8.9126, 61.8316)
  line L751 (-8.9126, 61.8316) -> (-8.8042, 62.2361)
  line L752 (-8.8042, 62.2361) -> (-8.6542, 62.6269)
  line L753 (-8.6542, 62.6269) -> (-8.4641, 63)
  line L754 (-8.4641, 63) -> (-8.2361, 63.3511)
  line L755 (-8.2361, 63.3511) -> (-7.9726, 63.6765)
  line L756 (-7.9726, 63.6765) -> (-7.6765, 63.9726)
  line L757 (-7.6765, 63.9726) -> (-7.3511, 64.2361)
  line L758 (-7.3511, 64.2361) -> (-7, 64.4641)
  line L759 (-7, 64.4641) -> (-6.6269, 64.6542)
  line L760 (-6.6269, 64.6542) -> (-6.2361, 64.8042)
  line L761 (-6.2361, 64.8042) -> (-5.8316, 64.9126)
  line L762 (-5.8316, 64.9126) -> (-5.4181, 64.9781)
  line L763 (-5.4181, 64.9781) -> (-5, 65)
  line L764 (-5, 65) -> (5, 65)
  line L765 (5, 65) -> (5.4181, 64.9781)
  line L766 (5.4181, 64.9781) -> (5.8316, 64.9126)
  line L767 (5.8316, 64.9126) -> (6.2361, 64.8042)
  line L768 (6.2361, 64.8042) -> (6.6269, 64.6542)
  line L769 (6.6269, 64.6542) -> (7, 64.4641)
  line L770 (7, 64.4641) -> (7.3511, 64.2361)
  line L771 (7.3511, 64.2361) -> (7.6765, 63.9726)
  line L772 (7.6765, 63.9726) -> (7.9726, 63.6765)
  line L773 (7.9726, 63.6765) -> (8.2361, 63.3511)
  line L774 (8.2361, 63.3511) -> (8.4641, 63)
  line L775 (8.4641, 63) -> (8.6542, 62.6269)
  line L776 (8.6542, 62.6269) -> (8.8042, 62.2361)
  line L777 (8.8042, 62.2361) -> (8.9126, 61.8316)
  line L778 (8.9126, 61.8316) -> (8.9781, 61.4181)
  line L779 (8.9781, 61.4181) -> (9, 61)
  line L780 (9, 61) -> (8.9781, 60.5819)
  line L781 (8.9781, 60.5819) -> (8.9126, 60.1684)
  line L782 (8.9126, 60.1684) -> (8.8042, 59.7639)
  line L783 (8.8042, 59.7639) -> (8.6542, 59.3731)
  line L784 (8.6542, 59.3731) -> (8.4641, 59)
  line L785 (8.4641, 59) -> (8.2361, 58.6489)
  line L786 (8.2361, 58.6489) -> (7.9726, 58.3235)
  line L787 (7.9726, 58.3235) -> (7.6765, 58.0274)
  line L788 (7.6765, 58.0274) -> (7.3511, 57.7639)
  line L789 (7.3511, 57.7639) -> (7, 57.5359)
  line L790 (7, 57.5359) -> (6.6269, 57.3458)
  line L791 (6.6269, 57.3458) -> (6.2361, 57.1958)
  line L792 (6.2361, 57.1958) -> (5.8316, 57.0874)
  line L793 (5.8316, 57.0874) -> (5.4181, 57.0219)
  line L794 (5.4181, 57.0219) -> (5, 57)
  line L795 (5, 57) -> (-5, 57)
  line L796 (-18.6672, 48.9088) -> (-18.8327, 48.935)
  line L797 (-18.8327, 48.935) -> (-18.9944, 48.9783)
  line L798 (-18.9944, 48.9783) -> (-19.1508, 49.0383)
  line L799 (-19.1508, 49.0383) -> (-19.3, 49.1144)
  line L800 (-19.3, 49.1144) -> (-19.4405, 49.2056)
  line L801 (-19.4405, 49.2056) -> (-19.5706, 49.311)
  line L802 (-19.5706, 49.311) -> (-19.689, 49.4294)
  line L803 (-19.689, 49.4294) -> (-19.7944, 49.5595)
  line L804 (-19.7944, 49.5595) -> (-19.8856, 49.7)
  line L805 (-19.8856, 49.7) -> (-19.9617, 49.8492)
  line L806 (-19.9617, 49.8492) -> (-20.0217, 50.0056)
  line L807 (-20.0217, 50.0056) -> (-20.065, 50.1673)
  line L808 (-20.065, 50.1673) -> (-20.0912, 50.3328)
  line L809 (-20.0912, 50.3328) -> (-20.1, 50.5)
  line L810 (-20.1, 50.5) -> (-20.0912, 50.6672)
  line L811 (-20.0912, 50.6672) -> (-20.065, 50.8327)
  line L812 (-20.065, 50.8327) -> (-20.0217, 50.9944)
  line L813 (-20.0217, 50.9944) -> (-19.9617, 51.1508)
  line L814 (-19.9617, 51.1508) -> (-19.8856, 51.3)
  line L815 (-19.8856, 51.3) -> (-19.7944, 51.4405)
  line L816 (-19.7944, 51.4405) -> (-19.689, 51.5706)
  line L817 (-19.689, 51.5706) -> (-19.5706, 51.689)
  line L818 (-19.5706, 51.689) -> (-19.4405, 51.7944)
  line L819 (-19.4405, 51.7944) -> (-19.3, 51.8856)
  line L820 (-19.3, 51.8856) -> (-19.1508, 51.9617)
  line L821 (-19.1508, 51.9617) -> (-18.9944, 52.0217)
  line L822 (-18.9944, 52.0217) -> (-18.8327, 52.065)
  line L823 (-18.8327, 52.065) -> (-18.6672, 52.0912)
  line L824 (-18.6672, 52.0912) -> (-18.5, 52.1)
  line L825 (-18.5, 52.1) -> (-18.3328, 52.0912)
  line L826 (-18.3328, 52.0912) -> (-18.1673, 52.065)
  line L827 (-18.1673, 52.065) -> (-18.0056, 52.0217)
  line L828 (-18.0056, 52.0217) -> (-17.8492, 51.9617)
  line L829 (-17.8492, 51.9617) -> (-17.7, 51.8856)
  line L830 (-17.7, 51.8856) -> (-17.5595, 51.7944)
  line L831 (-17.5595, 51.7944) -> (-17.4294, 51.689)
  line L832 (-17.4294, 51.689) -> (-17.311, 51.5706)
  line L833 (-17.311, 51.5706) -> (-17.2056, 51.4405)
  line L834 (-17.2056, 51.4405) -> (-17.1144, 51.3)
  line L835 (-17.1144, 51.3) -> (-17.0383, 51.1508)
  line L836 (-17.0383, 51.1508) -> (-16.9783, 50.9944)
  line L837 (-16.9783, 50.9944) -> (-16.935, 50.8327)
  line L838 (-16.935, 50.8327) -> (-16.9088, 50.6672)
  line L839 (-16.9088, 50.6672) -> (-16.9, 50.5)
  line L840 (-16.9, 50.5) -> (-16.9088, 50.3328)
  line L841 (-16.9088, 50.3328) -> (-16.935, 50.1673)
  line L842 (-16.935, 50.1673) -> (-16.9783, 50.0056)
  line L843 (-16.9783, 50.0056) -> (-17.0383, 49.8492)
  line L844 (-17.0383, 49.8492) -> (-17.1144, 49.7)
  line L845 (-17.1144, 49.7) -> (-17.2056, 49.5595)
  line L846 (-17.2056, 49.5595) -> (-17.311, 49.4294)
  line L847 (-17.311, 49.4294) -> (-17.4294, 49.311)
  line L848 (-17.4294, 49.311) -> (-17.5595, 49.2056)
  line L849 (-17.5595, 49.2056) -> (-17.7, 49.1144)
  line L850 (-17.7, 49.1144) -> (-17.8492, 49.0383)
  line L851 (-17.8492, 49.0383) -> (-18.0056, 48.9783)
  line L852 (-18.0056, 48.9783) -> (-18.1673, 48.935)
  line L853 (-18.1673, 48.935) -> (-18.3328, 48.9088)
  line L854 (-18.3328, 48.9088) -> (-18.5, 48.9)
  line L855 (-18.5, 48.9) -> (-18.6672, 48.9088)
  line L856 (18.3328, 48.9088) -> (18.1673, 48.935)
  line L857 (18.1673, 48.935) -> (18.0056, 48.9783)
  line L858 (18.0056, 48.9783) -> (17.8492, 49.0383)
  line L859 (17.8492, 49.0383) -> (17.7, 49.1144)
  line L860 (17.7, 49.1144) -> (17.5595, 49.2056)
  line L861 (17.5595, 49.2056) -> (17.4294, 49.311)
  line L862 (17.4294, 49.311) -> (17.311, 49.4294)
  line L863 (17.311, 49.4294) -> (17.2056, 49.5595)
  line L864 (17.2056, 49.5595) -> (17.1144, 49.7)
  line L865 (17.1144, 49.7) -> (17.0383, 49.8492)
  line L866 (17.0383, 49.8492) -> (16.9783, 50.0056)
  line L867 (16.9783, 50.0056) -> (16.935, 50.1673)
  line L868 (16.935, 50.1673) -> (16.9088, 50.3328)
  line L869 (16.9088, 50.3328) -> (16.9, 50.5)
  line L870 (16.9, 50.5) -> (16.9088, 50.6672)
  line L871 (16.9088, 50.6672) -> (16.935, 50.8327)
  line L872 (16.935, 50.8327) -> (16.9783, 50.9944)
  line L873 (16.9783, 50.9944) -> (17.0383, 51.1508)
  line L874 (17.0383, 51.1508) -> (17.1144, 51.3)
  line L875 (17.1144, 51.3) -> (17.2056, 51.4405)
  line L876 (17.2056, 51.4405) -> (17.311, 51.5706)
  line L877 (17.311, 51.5706) -> (17.4294, 51.689)
  line L878 (17.4294, 51.689) -> (17.5595, 51.7944)
  line L879 (17.5595, 51.7944) -> (17.7, 51.8856)
  line L880 (17.7, 51.8856) -> (17.8492, 51.9617)
  line L881 (17.8492, 51.9617) -> (18.0056, 52.0217)
  line L882 (18.0056, 52.0217) -> (18.1673, 52.065)
  line L883 (18.1673, 52.065) -> (18.3328, 52.0912)
  line L884 (18.3328, 52.0912) -> (18.5, 52.1)
  line L885 (18.5, 52.1) -> (18.6672, 52.0912)
  line L886 (18.6672, 52.0912) -> (18.8327, 52.065)
  line L887 (18.8327, 52.065) -> (18.9944, 52.0217)
  line L888 (18.9944, 52.0217) -> (19.1508, 51.9617)
  line L889 (19.1508, 51.9617) -> (19.3, 51.8856)
  line L890 (19.3, 51.8856) -> (19.4405, 51.7944)
  line L891 (19.4405, 51.7944) -> (19.5706, 51.689)
  line L892 (19.5706, 51.689) -> (19.689, 51.5706)
  line L893 (19.689, 51.5706) -> (19.7944, 51.4405)
  line L894 (19.7944, 51.4405) -> (19.8856, 51.3)
  line L895 (19.8856, 51.3) -> (19.9617, 51.1508)
  line L896 (19.9617, 51.1508) -> (20.0217, 50.9944)
  line L897 (20.0217, 50.9944) -> (20.065, 50.8327)
  line L898 (20.065, 50.8327) -> (20.0912, 50.6672)
  line L899 (20.0912, 50.6672) -> (20.1, 50.5)
  line L900 (20.1, 50.5) -> (20.0912, 50.3328)
  line L901 (20.0912, 50.3328) -> (20.065, 50.1673)
  line L902 (20.065, 50.1673) -> (20.0217, 50.0056)
  line L903 (20.0217, 50.0056) -> (19.9617, 49.8492)
  line L904 (19.9617, 49.8492) -> (19.8856, 49.7)
  line L905 (19.8856, 49.7) -> (19.7944, 49.5595)
  line L906 (19.7944, 49.5595) -> (19.689, 49.4294)
  line L907 (19.689, 49.4294) -> (19.5706, 49.311)
  line L908 (19.5706, 49.311) -> (19.4405, 49.2056)
  line L909 (19.4405, 49.2056) -> (19.3, 49.1144)
  line L910 (19.3, 49.1144) -> (19.1508, 49.0383)
  line L911 (19.1508, 49.0383) -> (18.9944, 48.9783)
  line L912 (18.9944, 48.9783) -> (18.8327, 48.935)
  line L913 (18.8327, 48.935) -> (18.6672, 48.9088)
  line L914 (18.6672, 48.9088) -> (18.5, 48.9)
  line L915 (18.5, 48.9) -> (18.3328, 48.9088)
  line L916 (-29.5, 26.5) -> (-29.5, 37.5)
  line L917 (-29.5, 37.5) -> (-27.5, 37.5)
  line L918 (-27.5, 37.5) -> (-27.5, 26.5)
  line L919 (-27.5, 26.5) -> (-29.5, 26.5)
  line L920 (27.5, 26.5) -> (27.5, 37.5)
  line L921 (27.5, 37.5) -> (29.5, 37.5)
  line L922 (29.5, 37.5) -> (29.5, 26.5)
  line L923 (29.5, 26.5) -> (27.5, 26.5)
  line L924 (-18.6672, 11.9088) -> (-18.8327, 11.935)
  line L925 (-18.8327, 11.935) -> (-18.9944, 11.9783)
  line L926 (-18.9944, 11.9783) -> (-19.1508, 12.0383)
  line L927 (-19.1508, 12.0383) -> (-19.3, 12.1144)
  line L928 (-19.3, 12.1144) -> (-19.4405, 12.2056)
  line L929 (-19.4405, 12.2056) -> (-19.5706, 12.311)
  line L930 (-19.5706, 12.311) -> (-19.689, 12.4294)
  line L931 (-19.689, 12.4294) -> (-19.7944, 12.5595)
  line L932 (-19.7944, 12.5595) -> (-19.8856, 12.7)
  line L933 (-19.8856, 12.7) -> (-19.9617, 12.8492)
  line L934 (-19.9617, 12.8492) -> (-20.0217, 13.0056)
  line L935 (-20.0217, 13.0056) -> (-20.065, 13.1673)
  line L936 (-20.065, 13.1673) -> (-20.0912, 13.3328)
  line L937 (-20.0912, 13.3328) -> (-20.1, 13.5)
  line L938 (-20.1, 13.5) -> (-20.0912, 13.6672)
  line L939 (-20.0912, 13.6672) -> (-20.065, 13.8327)
  line L940 (-20.065, 13.8327) -> (-20.0217, 13.9944)
  line L941 (-20.0217, 13.9944) -> (-19.9617, 14.1508)
  line L942 (-19.9617, 14.1508) -> (-19.8856, 14.3)
  line L943 (-19.8856, 14.3) -> (-19.7944, 14.4405)
  line L944 (-19.7944, 14.4405) -> (-19.689, 14.5706)
  line L945 (-19.689, 14.5706) -> (-19.5706, 14.689)
  line L946 (-19.5706, 14.689) -> (-19.4405, 14.7944)
  line L947 (-19.4405, 14.7944) -> (-19.3, 14.8856)
  line L948 (-19.3, 14.8856) -> (-19.1508, 14.9617)
  line L949 (-19.1508, 14.9617) -> (-18.9944, 15.0217)
  line L950 (-18.9944, 15.0217) -> (-18.8327, 15.065)
  line L951 (-18.8327, 15.065) -> (-18.6672, 15.0912)
  line L952 (-18.6672, 15.0912) -> (-18.5, 15.1)
  line L953 (-18.5, 15.1) -> (-18.3328, 15.0912)
  line L954 (-18.3328, 15.0912) -> (-18.1673, 15.065)
  line L955 (-18.1673, 15.065) -> (-18.0056, 15.0217)
  line L956 (-18.0056, 15.0217) -> (-17.8492, 14.9617)
  line L957 (-17.8492, 14.9617) -> (-17.7, 14.8856)
  line L958 (-17.7, 14.8856) -> (-17.5595, 14.7944)
  line L959 (-17.5595, 14.7944) -> (-17.4294, 14.689)
  line L960 (-17.4294, 14.689) -> (-17.311, 14.5706)
  line L961 (-17.311, 14.5706) -> (-17.2056, 14.4405)
  line L962 (-17.2056, 14.4405) -> (-17.1144, 14.3)
  line L963 (-17.1144, 14.3) -> (-17.0383, 14.1508)
  line L964 (-17.0383, 14.1508) -> (-16.9783, 13.9944)
  line L965 (-16.9783, 13.9944) -> (-16.935, 13.8327)
  line L966 (-16.935, 13.8327) -> (-16.9088, 13.6672)
  line L967 (-16.9088, 13.6672) -> (-16.9, 13.5)